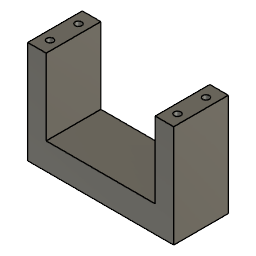
Base Robot arm Servo mount (Autodesk Fusion 360 design; units mm, degrees)
Autodesk Fusion 360 part; units mm, degrees
sketch "Sketch1" plane through (0, 0, 0) normal (0, 0, 1) x (1, 0, 0)
  line L0 (0, 0) -> (7, 0)
  line L1 (7, 0) -> (7, 20.6)
  line L2 (7, 20.6) -> (0, 20.6)
  line L3 (0, 20.6) -> (0, 0)
  line L4 (7, 0) -> (48, 0) construction
  line L5 (48, 0) -> (48, 20.6) construction
  line L6 (48, 20.6) -> (7, 20.6) construction
  line L7 (7, 20.6) -> (7, 0) construction
  circle A0 centre (3.5, 15.66) radius 1.25
  line L8 (0, 10.3) -> (7, 10.3) construction
  circle A1 centre (3.5, 4.94) radius 1.25
  line L9 (27.5, 0) -> (27.5, 20.6) construction
  line L10 (7, 20.6) -> (48, 20.6) construction
  line L11 (55, 20.6) -> (55, 0)
  circle A2 centre (51.5, 4.94) radius 1.25
  line L12 (48, 20.6) -> (48, 0) construction
  line L13 (55, 10.3) -> (48, 10.3) construction
  line L14 (48, 0) -> (48, 20.6)
  line L15 (48, 20.6) -> (55, 20.6)
  circle A3 centre (51.5, 15.66) radius 1.25
  line L16 (55, 0) -> (48, 0)
  dimension "d1" = 7
  dimension "d2" = 20.6
  dimension "d3" = 41
  dimension "d5" = 2.5
  dimension "d6" = 3.5
  dimension "d7" = 4.94
  constraint horizontal L0
  constraint vertical L1
  constraint horizontal L2
  constraint vertical L3
  constraint coincident L0.start L3.end
  constraint horizontal L4
  constraint vertical L5
  constraint horizontal L6
  constraint vertical L7
  constraint midpoint L3 L8.start
  constraint midpoint L1 L8.end
  constraint symmetric A0 L8 A1
  constraint midpoint L4 L9.start
  constraint midpoint L6 L9.end
  constraint symmetric L0.start L9 L11.end
  constraint symmetric L0.end L9 L4.end
  constraint symmetric L1.end L9 L5.end
  constraint symmetric L2.end L9 L11.start
  constraint symmetric L1.end L5.end L9
  constraint symmetric A0 L9 A3
  constraint symmetric L8.start L9 L13.start
  constraint symmetric L8.end L9 L13.end
  constraint symmetric A1 L9 A2
  measures "d1" distance of L0.start L0.end
  measures "d2" distance of L0.start L2.end
  measures "d3" distance of L0.end L4.end
  measures "d5" diameter of A0
  measures "d6" distance of L7 A0.centre
  measures "d7" distance of L2 A0.centre
extrude "Extrude1" add sketch "Sketch1" along normal blind 10 makes body 1 at (0, 13.7333, 3.3333) makes body 2 at (55, 13.7333, 3.3333)
ref_plane "WorkPlane1" through (51.5, 10.3, -18.6) normal (0, 0, 1) x (1, 0, 0)
sketch "Sketch2" plane through (0, 0, -18.6) normal (0, 0, 1) x (1, 0, 0)
  line L0 (0, 0) -> (55, 0)
  line L1 (55, 0) -> (55, 20.6)
  line L2 (55, 20.6) -> (0, 20.6)
  line L3 (0, 20.6) -> (0, 0)
  dimension "d11" = 55
  dimension "d12" = 20.6
  constraint horizontal L0
  constraint vertical L1
  constraint horizontal L2
  constraint vertical L3
  constraint coincident L0.start L3.end
  measures "d11" distance of L0.start L0.end
  measures "d12" distance of L0.start L2.end
extrude "Extrude2" add sketch "Sketch2" against normal blind 10 separate body makes body 3
sketch "Sketch4" plane through (0, 0, -18.6) normal (0, 0, 1) x (-1, 0, 0)
  line L0 (0, -20.6) -> (0, 0)
  line L1 (0, 0) -> (-55, 0)
  line L2 (-55, 0) -> (-55, -20.6)
  line L3 (-55, -20.6) -> (0, -20.6)
  line L4 (0, 0) -> (-7, 0)
  line L5 (-7, 0) -> (-7, -20.6)
  line L6 (-7, -20.6) -> (0, -20.6)
  line L7 (0, -20.6) -> (0, 0)
  line L8 (-55, 0) -> (-48, 0)
  line L9 (-48, 0) -> (-48, -20.6)
  line L10 (-48, -20.6) -> (-55, -20.6)
  line L11 (-55, -20.6) -> (-55, 0)
  dimension "d19" = 7
  dimension "d20" = 7
  constraint horizontal L4
  constraint vertical L5
  constraint horizontal L6
  constraint vertical L7
  constraint coincident L0.end L1.start
  constraint horizontal L8
  constraint vertical L9
  constraint horizontal L10
  constraint vertical L11
  constraint coincident L1.end L2.start
  constraint coincident L2.end L3.start
  measures "d19" distance of L0.end L4.end
  measures "d20" distance of L1.end L8.end
extrude "Extrude4" add sketch "Sketch4" along normal blind 19 contours L0 L1 L3 L4 L5 L6 L7 | L1 L2 L3 L8 L9 L10 L11 bodies 1 2 3
